Autodesk Fusion 360 part; units mm, degrees
(part 2 of 2)
  spline S171 degree 3 poles (-47.6297, 29.4828) (-47.5303, 29.3502) (-47.5255, 29.3502) (-46.4124, 28.9712) knots 0 0 0 0 1 1 1 1
  spline S172 degree 3 poles (-46.4124, 28.9712) (-46.0051, 28.8339) (-45.6546, 28.706) (-45.6403, 28.6918) knots 0 0 0 0 1 1 1 1
  spline S173 degree 3 poles (-45.6403, 28.6918) (-45.6072, 28.6586) (-45.5835, 28.6634) (-46.6398, 28.4692) knots 0 0 0 0 1 1 1 1
  spline S174 degree 3 poles (-46.6398, 28.4692) (-48.1413, 28.1944) (-48.7571, 28.0571) (-48.8281, 27.9813) knots 0 0 0 0 1 1 1 1
  spline S175 degree 3 poles (-48.8281, 27.9813) (-48.9086, 27.9008) (-48.9228, 27.6308) (-48.8518, 27.5597) knots 0 0 0 0 1 1 1 1
  spline S176 degree 3 poles (-48.8518, 27.5597) (-48.8281, 27.536) (-48.3308, 27.3561) (-47.7481, 27.1619) knots 0 0 0 0 1 1 1 1
  spline S177 degree 3 poles (-47.7481, 27.1619) (-47.1655, 26.9676) (-46.6824, 26.7971) (-46.6729, 26.7877) knots 0 0 0 0 1 1 1 1
  spline S178 degree 3 poles (-46.6729, 26.7877) (-46.6635, 26.7782) (-46.7392, 26.7261) (-46.8387, 26.674) knots 0 0 0 0 1 1 1 1
  spline S179 degree 3 poles (-46.8387, 26.674) (-47.1561, 26.5129) (-47.1561, 26.5129) (-47.1845, 25.4993) knots 0 0 0 0 1 1 1 1
  line L126 (-47.1845, 25.4993) -> (-47.2082, 24.5804)
  line L127 (-47.2082, 24.5804) -> (-47.6818, 24.9783)
  spline S180 degree 3 poles (-47.6818, 24.9783) (-48.9465, 26.0487) (-50.5001, 27.6355) (-50.5807, 27.9387) knots 0 0 0 0 1 1 1 1
  spline S181 degree 3 poles (-50.5807, 27.9387) (-50.5949, 28.005) (-50.5712, 28.1187) (-50.5191, 28.2181) knots 0 0 0 0 1 1 1 1
  spline S182 degree 3 poles (-50.5191, 28.2181) (-50.3154, 28.6018) (-48.6813, 30.2549) (-47.8334, 30.9322) knots 0 0 0 0 1 1 1 1
  line L128 (-47.8334, 30.9322) -> (-47.5682, 31.1454)
  line L129 (-47.5682, 31.1454) -> (-47.5634, 31.5669)
  line L130 (-47.5634, 31.5669) -> (-47.5634, 31.9838)
  line L131 (-47.5634, 31.9838) -> (-47.7908, 31.8038)
  spline S183 degree 3 poles (-47.7908, 31.8038) (-48.3071, 31.3869) (-49.387, 30.3733) (-50.0786, 29.6675) knots 0 0 0 0 1 1 1 1
  spline S184 degree 3 poles (-50.0786, 29.6675) (-51.3385, 28.3697) (-51.4759, 28.0381) (-51.0022, 27.3939) knots 0 0 0 0 1 1 1 1
  spline S185 degree 3 poles (-51.0022, 27.3939) (-50.5143, 26.7261) (-48.6386, 24.9214) (-47.3976, 23.922) knots 0 0 0 0 1 1 1 1
  spline S186 degree 3 poles (-47.3976, 23.922) (-46.0572, 22.842) (-45.5219, 22.5957) (-44.5035, 22.5957) knots 0 0 0 0 1 1 1 1
  spline S187 degree 3 poles (-44.5035, 22.5957) (-44.0583, 22.5957) (-43.9352, 22.6147) (-43.5941, 22.7331) knots 0 0 0 0 1 1 1 1
  spline S188 degree 3 poles (-43.5941, 22.7331) (-42.5521, 23.0978) (-41.8463, 23.903) (-41.6237, 24.9783) knots 0 0 0 0 1 1 1 1
  spline S189 degree 3 poles (-41.6237, 24.9783) (-41.4295, 25.9066) (-41.6521, 26.7545) (-42.3152, 27.6213) knots 0 0 0 0 1 1 1 1
  line L132 (-42.3152, 27.6213) -> (-42.6278, 28.0334)
  line L133 (-42.6278, 28.0334) -> (-42.4857, 28.166)
  spline S190 degree 3 poles (-42.4857, 28.166) (-42.32, 28.3271) (-41.9837, 28.8291) (-41.8416, 29.1323) knots 0 0 0 0 1 1 1 1
  spline S191 degree 3 poles (-41.8416, 29.1323) (-41.6095, 29.6249) (-41.5005, 30.4396) (-41.6, 30.9748) knots 0 0 0 0 1 1 1 1
  spline S192 degree 3 poles (-42.3152, 24.8267) (-42.4431, 24.4478) (-42.6136, 24.1825) (-42.9262, 23.8746) knots 0 0 0 0 1 1 1 1
  spline S193 degree 3 poles (-42.9262, 23.8746) (-43.4236, 23.382) (-43.9873, 23.1783) (-44.7214, 23.2257) knots 0 0 0 0 1 1 1 1
  spline S194 degree 3 poles (-44.7214, 23.2257) (-45.1998, 23.2541) (-45.5693, 23.3773) (-46.0003, 23.6615) knots 0 0 0 0 1 1 1 1
  spline S195 degree 3 poles (-46.0003, 23.6615) (-46.545, 24.0215) (-46.5119, 23.9315) (-46.5308, 25.144) knots 0 0 0 0 1 1 1 1
  line L134 (-46.5308, 25.144) -> (-46.545, 26.1956)
  line L135 (-46.545, 26.1956) -> (-46.223, 26.3661)
  spline S196 degree 3 poles (-46.223, 26.3661) (-46.0477, 26.4561) (-45.8724, 26.584) (-45.8298, 26.6456) knots 0 0 0 0 1 1 1 1
  spline S197 degree 3 poles (-45.8298, 26.6456) (-45.7351, 26.7924) (-45.7777, 27.015) (-45.9245, 27.1097) knots 0 0 0 0 1 1 1 1
  spline S198 degree 3 poles (-45.9245, 27.1097) (-45.9814, 27.1476) (-46.384, 27.2945) (-46.8198, 27.4318) knots 0 0 0 0 1 1 1 1
  spline S199 degree 3 poles (-46.8198, 27.4318) (-47.5587, 27.6639) (-47.7529, 27.7587) (-47.5066, 27.7587) knots 0 0 0 0 1 1 1 1
  spline S200 degree 3 poles (-47.5066, 27.7587) (-47.4071, 27.7587) (-47.0945, 27.8155) (-46.0951, 28.0192) knots 0 0 0 0 1 1 1 1
  spline S201 degree 3 poles (-46.0951, 28.0192) (-44.7546, 28.2892) (-44.5509, 28.3413) (-44.4704, 28.4123) knots 0 0 0 0 1 1 1 1
  spline S202 degree 3 poles (-44.4704, 28.4123) (-44.3472, 28.5213) (-44.3662, 28.7818) (-44.4988, 28.8718) knots 0 0 0 0 1 1 1 1
  spline S203 degree 3 poles (-44.4988, 28.8718) (-44.5888, 28.9286) (-46.815, 29.7007) (-46.9003, 29.7007) knots 0 0 0 0 1 1 1 1
  spline S204 degree 3 poles (-46.9003, 29.7007) (-46.9098, 29.7007) (-46.8435, 29.7528) (-46.7535, 29.8144) knots 0 0 0 0 1 1 1 1
  spline S205 degree 3 poles (-46.7535, 29.8144) (-46.5403, 29.9612) (-46.5214, 30.0749) (-46.5214, 31.169) knots 0 0 0 0 1 1 1 1
  line L136 (-46.5214, 31.169) -> (-46.5214, 31.9648)
  line L137 (-46.5214, 31.9648) -> (-46.223, 32.1874)
  spline S206 degree 3 poles (-46.223, 32.1874) (-45.6688, 32.5995) (-45.1572, 32.7795) (-44.5414, 32.7795) knots 0 0 0 0 1 1 1 1
  spline S207 degree 3 poles (-44.5414, 32.7795) (-43.6367, 32.7795) (-42.8078, 32.249) (-42.4147, 31.4248) knots 0 0 0 0 1 1 1 1
  spline S208 degree 3 poles (-42.4147, 31.4248) (-42.2489, 31.0791) (-42.2347, 31.0127) (-42.2205, 30.5485) knots 0 0 0 0 1 1 1 1
  spline S209 degree 3 poles (-42.2205, 30.5485) (-42.1921, 29.767) (-42.3436, 29.3454) (-42.9026, 28.6492) knots 0 0 0 0 1 1 1 1
  spline S210 degree 3 poles (-42.9026, 28.6492) (-43.0778, 28.436) (-43.2341, 28.2086) (-43.2531, 28.1423) knots 0 0 0 0 1 1 1 1
  spline S211 degree 3 poles (-43.2531, 28.1423) (-43.3052, 27.9434) (-43.2247, 27.7539) (-42.9405, 27.4271) knots 0 0 0 0 1 1 1 1
  spline S212 degree 3 poles (-42.9405, 27.4271) (-42.6563, 27.0955) (-42.4005, 26.6645) (-42.3057, 26.3614) knots 0 0 0 0 1 1 1 1
  spline S213 degree 3 poles (-42.3057, 26.3614) (-42.1542, 25.8877) (-42.1542, 25.2814) (-42.3152, 24.8267) knots 0 0 0 0 1 1 1 1
  line L138 (-47.5871, 5.9227) -> (-49.226, 5.9227)
  line L139 (-49.226, 5.9227) -> (-49.2118, 5.648)
  spline S214 degree 3 poles (-49.2118, 5.648) (-49.1976, 5.3828) (-49.1976, 5.378) (-49.0365, 5.3544) knots 0 0 0 0 1 1 1 1
  line L140 (-49.0365, 5.3544) -> (-48.8802, 5.3307)
  line L141 (-48.8802, 5.3307) -> (-48.9844, 5.2359)
  spline S215 degree 3 poles (-48.9844, 5.2359) (-49.3586, 4.9044) (-49.2733, 4.1986) (-48.8281, 3.8907) knots 0 0 0 0 1 1 1 1
  spline S216 degree 3 poles (-48.8281, 3.8907) (-48.5344, 3.6918) (-48.3071, 3.635) (-47.9234, 3.6586) knots 0 0 0 0 1 1 1 1
  spline S217 degree 3 poles (-47.9234, 3.6586) (-47.4118, 3.6918) (-47.085, 3.8955) (-46.924, 4.2744) knots 0 0 0 0 1 1 1 1
  spline S218 degree 3 poles (-46.924, 4.2744) (-46.7913, 4.6012) (-46.8482, 4.9328) (-47.0803, 5.1744) knots 0 0 0 0 1 1 1 1
  line L142 (-47.0803, 5.1744) -> (-47.2034, 5.307)
  line L143 (-47.2034, 5.307) -> (-46.5782, 5.307)
  line L144 (-46.5782, 5.307) -> (-45.953, 5.307)
  line L145 (-45.953, 5.307) -> (-45.953, 5.6149)
  line L146 (-45.953, 5.6149) -> (-45.953, 5.9227)
  line L147 (-45.953, 5.9227) -> (-47.5871, 5.9227)
  spline S219 degree 3 poles (-47.4876, 4.4875) (-47.7245, 4.2318) (-48.2787, 4.2128) (-48.5202, 4.4591) knots 0 0 0 0 1 1 1 1
  spline S220 degree 3 poles (-48.5202, 4.4591) (-48.7097, 4.6439) (-48.7097, 4.9517) (-48.5202, 5.1317) knots 0 0 0 0 1 1 1 1
  spline S221 degree 3 poles (-48.5202, 5.1317) (-48.2692, 5.3686) (-47.6724, 5.3449) (-47.4734, 5.0844) knots 0 0 0 0 1 1 1 1
  spline S222 degree 3 poles (-47.4734, 5.0844) (-47.3361, 4.9138) (-47.3408, 4.6439) (-47.4876, 4.4875) knots 0 0 0 0 1 1 1 1
  spline S223 degree 3 poles (-46.1282, 21.8568) (-46.2372, 21.89) (-49.027, 21.89) (-49.136, 21.8568) knots 0 0 0 0 1 1 1 1
  spline S224 degree 3 poles (-49.136, 21.8568) (-49.207, 21.8379) (-49.2212, 21.7763) (-49.2212, 21.5252) knots 0 0 0 0 1 1 1 1
  line L148 (-49.2212, 21.5252) -> (-49.2212, 21.2221)
  line L149 (-49.2212, 21.2221) -> (-48.5107, 21.2221)
  line L150 (-48.5107, 21.2221) -> (-47.7955, 21.2221)
  line L151 (-47.7955, 21.2221) -> (-47.8097, 20.4974)
  line L152 (-47.8097, 20.4974) -> (-47.8239, 19.7774)
  line L153 (-47.8239, 19.7774) -> (-48.525, 19.7632)
  line L154 (-48.525, 19.7632) -> (-49.226, 19.749)
  line L155 (-49.226, 19.749) -> (-49.2118, 19.4317)
  line L156 (-49.2118, 19.4317) -> (-49.1976, 19.1143)
  line L157 (-49.1976, 19.1143) -> (-47.6203, 19.1001)
  line L158 (-47.6203, 19.1001) -> (-46.0477, 19.0906)
  line L159 (-46.0477, 19.0906) -> (-46.0477, 19.4222)
  line L160 (-46.0477, 19.4222) -> (-46.0477, 19.749)
  line L161 (-46.0477, 19.749) -> (-46.6256, 19.7632)
  line L162 (-46.6256, 19.7632) -> (-47.2082, 19.7774)
  line L163 (-47.2082, 19.7774) -> (-47.2082, 20.4879)
  line L164 (-47.2082, 20.4879) -> (-47.2082, 21.1984)
  line L165 (-47.2082, 21.1984) -> (-46.6256, 21.2126)
  line L166 (-46.6256, 21.2126) -> (-46.0477, 21.2268)
  line L167 (-46.0477, 21.2268) -> (-46.0477, 21.53)
  spline S225 degree 3 poles (-46.0477, 21.53) (-46.0477, 21.7763) (-46.0619, 21.8379) (-46.1282, 21.8568) knots 0 0 0 0 1 1 1 1
  line L168 (-47.6345, 10.4699) -> (-49.2212, 10.4699)
  line L169 (-49.2212, 10.4699) -> (-49.2212, 9.5463)
  line L170 (-49.2212, 9.5463) -> (-49.2212, 8.6226)
  line L171 (-49.2212, 8.6226) -> (-48.9134, 8.6226)
  line L172 (-48.9134, 8.6226) -> (-48.6055, 8.6226)
  line L173 (-48.6055, 8.6226) -> (-48.6055, 9.2384)
  line L174 (-48.6055, 9.2384) -> (-48.6055, 9.8542)
  line L175 (-48.6055, 9.8542) -> (-47.3266, 9.8542)
  line L176 (-47.3266, 9.8542) -> (-46.0477, 9.8542)
  line L177 (-46.0477, 9.8542) -> (-46.0477, 10.162)
  line L178 (-46.0477, 10.162) -> (-46.0477, 10.4699)
  line L179 (-46.0477, 10.4699) -> (-47.6345, 10.4699)
  spline S226 degree 3 poles (-46.3603, 11.9714) (-46.3793, 12.0093) (-46.4835, 12.033) (-46.6398, 12.033) knots 0 0 0 0 1 1 1 1
  spline S227 degree 3 poles (-46.6398, 12.033) (-46.8908, 12.033) (-46.8956, 12.033) (-46.9098, 12.1846) knots 0 0 0 0 1 1 1 1
  spline S228 degree 3 poles (-46.9098, 12.1846) (-46.9192, 12.2698) (-46.9382, 12.3362) (-46.9571, 12.3267) knots 0 0 0 0 1 1 1 1
  spline S229 degree 3 poles (-46.9571, 12.3267) (-46.9808, 12.322) (-47.0803, 12.3172) (-47.1845, 12.3172) knots 0 0 0 0 1 1 1 1
  spline S230 degree 3 poles (-47.1845, 12.3172) (-47.3597, 12.3172) (-47.374, 12.3077) (-47.374, 12.1799) knots 0 0 0 0 1 1 1 1
  line L180 (-47.374, 12.1799) -> (-47.374, 12.0425)
  line L181 (-47.374, 12.0425) -> (-48.0466, 12.0235)
  spline S231 degree 3 poles (-48.0466, 12.0235) (-48.8044, 12.0046) (-48.937, 11.9667) (-49.1123, 11.7062) knots 0 0 0 0 1 1 1 1
  spline S232 degree 3 poles (-49.1123, 11.7062) (-49.1928, 11.5878) (-49.2212, 11.4788) (-49.2212, 11.2799) knots 0 0 0 0 1 1 1 1
  spline S233 degree 3 poles (-49.2212, 11.2799) (-49.2212, 10.8299) (-49.2023, 10.8015) (-48.9086, 10.8015) knots 0 0 0 0 1 1 1 1
  line L182 (-48.9086, 10.8015) -> (-48.6528, 10.8015)
  line L183 (-48.6528, 10.8015) -> (-48.6528, 11.0288)
  spline S234 degree 3 poles (-48.6528, 11.0288) (-48.6528, 11.152) (-48.6292, 11.2799) (-48.596, 11.313) knots 0 0 0 0 1 1 1 1
  spline S235 degree 3 poles (-48.596, 11.313) (-48.5581, 11.3509) (-48.345, 11.3699) (-47.9566, 11.3699) knots 0 0 0 0 1 1 1 1
  line L184 (-47.9566, 11.3699) -> (-47.374, 11.3699)
  line L185 (-47.374, 11.3699) -> (-47.374, 11.081)
  line L186 (-47.374, 11.081) -> (-47.374, 10.7968)
  line L187 (-47.374, 10.7968) -> (-47.1466, 10.811)
  line L188 (-47.1466, 10.811) -> (-46.924, 10.8252)
  line L189 (-46.924, 10.8252) -> (-46.9098, 11.0952)
  line L190 (-46.9098, 11.0952) -> (-46.8956, 11.3651)
  line L191 (-46.8956, 11.3651) -> (-46.6256, 11.3794)
  line L192 (-46.6256, 11.3794) -> (-46.3556, 11.3936)
  line L193 (-46.3556, 11.3936) -> (-46.3461, 11.6541)
  spline S236 degree 3 poles (-46.3461, 11.6541) (-46.3414, 11.7962) (-46.3508, 11.943) (-46.3603, 11.9714) knots 0 0 0 0 1 1 1 1
  spline S237 degree 3 poles (-46.9145, 18.0864) (-47.0755, 18.527) (-47.5113, 18.8064) (-48.0371, 18.8064) knots 0 0 0 0 1 1 1 1
  spline S238 degree 3 poles (-48.0371, 18.8064) (-48.7665, 18.8017) (-49.2212, 18.3422) (-49.2212, 17.608) knots 0 0 0 0 1 1 1 1
  spline S239 degree 3 poles (-49.2212, 17.608) (-49.2212, 17.4328) (-49.1928, 17.2196) (-49.1597, 17.1344) knots 0 0 0 0 1 1 1 1
  spline S240 degree 3 poles (-49.1597, 17.1344) (-49.0791, 16.9497) (-48.8518, 16.6749) (-48.7807, 16.6749) knots 0 0 0 0 1 1 1 1
  spline S241 degree 3 poles (-48.7807, 16.6749) (-48.7476, 16.6749) (-48.6765, 16.7507) (-48.615, 16.8454) knots 0 0 0 0 1 1 1 1
  line L194 (-48.615, 16.8454) -> (-48.506, 17.0112)
  line L195 (-48.506, 17.0112) -> (-48.6007, 17.2149)
  spline S242 degree 3 poles (-48.6007, 17.2149) (-48.7713, 17.5654) (-48.705, 17.9396) (-48.4444, 18.1149) knots 0 0 0 0 1 1 1 1
  spline S243 degree 3 poles (-48.4444, 18.1149) (-48.1887, 18.2806) (-48.1792, 18.2617) (-48.1792, 17.4091) knots 0 0 0 0 1 1 1 1
  line L196 (-48.1792, 17.4091) -> (-48.1792, 16.6276)
  line L197 (-48.1792, 16.6276) -> (-47.895, 16.6276)
  spline S244 degree 3 poles (-47.895, 16.6276) (-47.2745, 16.6276) (-46.8529, 17.0539) (-46.8577, 17.6696) knots 0 0 0 0 1 1 1 1
  spline S245 degree 3 poles (-46.8577, 17.6696) (-46.8577, 17.8117) (-46.8861, 18.0012) (-46.9145, 18.0864) knots 0 0 0 0 1 1 1 1
  spline S246 degree 3 poles (-47.374, 17.4281) (-47.4355, 17.3238) (-47.6913, 17.1817) (-47.7529, 17.2196) knots 0 0 0 0 1 1 1 1
  spline S247 degree 3 poles (-47.7529, 17.2196) (-47.8192, 17.2623) (-47.8145, 18.1907) (-47.7481, 18.1907) knots 0 0 0 0 1 1 1 1
  spline S248 degree 3 poles (-47.7481, 18.1907) (-47.6629, 18.1907) (-47.4971, 18.0912) (-47.4118, 17.9822) knots 0 0 0 0 1 1 1 1
  spline S249 degree 3 poles (-47.4118, 17.9822) (-47.3171, 17.8733) (-47.2982, 17.5702) (-47.374, 17.4281) knots 0 0 0 0 1 1 1 1
  spline S250 degree 3 poles (-46.8956, 15.7276) (-46.9666, 15.9502) (-47.0898, 16.1539) (-47.2129, 16.2297) knots 0 0 0 0 1 1 1 1
  spline S251 degree 3 poles (-47.2129, 16.2297) (-47.3503, 16.3197) (-47.3313, 16.3292) (-47.464, 16.0734) knots 0 0 0 0 1 1 1 1
  line L198 (-47.464, 16.0734) -> (-47.5634, 15.8744)
  line L199 (-47.5634, 15.8744) -> (-47.445, 15.756)
  spline S252 degree 3 poles (-47.445, 15.756) (-47.2745, 15.5855) (-47.2745, 15.2066) (-47.445, 15.0408) knots 0 0 0 0 1 1 1 1
  spline S253 degree 3 poles (-47.445, 15.0408) (-47.5066, 14.9745) (-47.6108, 14.9224) (-47.6771, 14.9224) knots 0 0 0 0 1 1 1 1
  spline S254 degree 3 poles (-47.6771, 14.9224) (-47.7908, 14.9224) (-47.7955, 14.9271) (-47.7955, 15.3487) knots 0 0 0 0 1 1 1 1
  spline S255 degree 3 poles (-47.7955, 15.3487) (-47.7955, 15.7087) (-47.8097, 15.8081) (-47.9045, 15.9739) knots 0 0 0 0 1 1 1 1
  spline S256 degree 3 poles (-47.9045, 15.9739) (-48.1981, 16.5091) (-48.8707, 16.5328) (-49.1407, 16.0118) knots 0 0 0 0 1 1 1 1
  spline S257 degree 3 poles (-49.1407, 16.0118) (-49.2686, 15.7608) (-49.2355, 15.3155) (-49.0649, 15.0976) knots 0 0 0 0 1 1 1 1
  spline S258 degree 3 poles (-49.0649, 15.0976) (-48.9939, 15.0029) (-48.937, 14.9176) (-48.937, 14.9034) knots 0 0 0 0 1 1 1 1
  spline S259 degree 3 poles (-48.937, 14.9034) (-48.937, 14.8892) (-48.9986, 14.875) (-49.0791, 14.875) knots 0 0 0 0 1 1 1 1
  line L200 (-49.0791, 14.875) -> (-49.2212, 14.875)
  line L201 (-49.2212, 14.875) -> (-49.2212, 14.5908)
  line L202 (-49.2212, 14.5908) -> (-49.2212, 14.3066)
  line L203 (-49.2212, 14.3066) -> (-48.3781, 14.3066)
  spline S260 degree 3 poles (-48.3781, 14.3066) (-47.4829, 14.3066) (-47.2792, 14.3492) (-47.0755, 14.5813) knots 0 0 0 0 1 1 1 1
  spline S261 degree 3 poles (-47.0755, 14.5813) (-46.8861, 14.7945) (-46.7913, 15.3866) (-46.8956, 15.7276) knots 0 0 0 0 1 1 1 1
  spline S262 degree 3 poles (-48.2502, 14.9413) (-48.3781, 14.8892) (-48.5534, 14.9697) (-48.6292, 15.1118) knots 0 0 0 0 1 1 1 1
  spline S263 degree 3 poles (-48.6292, 15.1118) (-48.7239, 15.2918) (-48.7192, 15.6044) (-48.6244, 15.6992) knots 0 0 0 0 1 1 1 1
  spline S264 degree 3 poles (-48.6244, 15.6992) (-48.5202, 15.8081) (-48.3402, 15.7939) (-48.255, 15.6708) knots 0 0 0 0 1 1 1 1
  spline S265 degree 3 poles (-48.255, 15.6708) (-48.1508, 15.5239) (-48.1508, 14.9792) (-48.2502, 14.9413) knots 0 0 0 0 1 1 1 1
  spline S266 degree 3 poles (-46.8861, 12.8714) (-46.8956, 12.9282) (-46.9808, 13.0419) (-47.0708, 13.1177) knots 0 0 0 0 1 1 1 1
  spline S267 degree 3 poles (-47.0708, 13.1177) (-47.1608, 13.1982) (-47.2319, 13.274) (-47.2319, 13.2882) knots 0 0 0 0 1 1 1 1
  spline S268 degree 3 poles (-47.2319, 13.2882) (-47.2319, 13.3024) (-47.1561, 13.3119) (-47.0661, 13.3119) knots 0 0 0 0 1 1 1 1
  line L204 (-47.0661, 13.3119) -> (-46.9003, 13.3119)
  line L205 (-46.9003, 13.3119) -> (-46.9003, 13.5961)
  line L206 (-46.9003, 13.5961) -> (-46.9003, 13.8803)
  line L207 (-46.9003, 13.8803) -> (-48.0608, 13.8803)
  line L208 (-48.0608, 13.8803) -> (-49.2212, 13.8803)
  line L209 (-49.2212, 13.8803) -> (-49.2212, 13.5724)
  line L210 (-49.2212, 13.5724) -> (-49.2212, 13.2645)
  line L211 (-49.2212, 13.2645) -> (-48.6055, 13.2645)
  spline S269 degree 3 poles (-48.6055, 13.2645) (-47.7481, 13.2645) (-47.5682, 13.1793) (-47.5161, 12.7482) knots 0 0 0 0 1 1 1 1
  line L212 (-47.5161, 12.7482) -> (-47.4924, 12.5304)
  line L213 (-47.4924, 12.5304) -> (-47.1703, 12.5162)
  line L214 (-47.1703, 12.5162) -> (-46.8529, 12.5019)
  line L215 (-46.8529, 12.5019) -> (-46.8577, 12.6346)
  spline S270 degree 3 poles (-46.8577, 12.6346) (-46.8624, 12.7056) (-46.8766, 12.8146) (-46.8861, 12.8714) knots 0 0 0 0 1 1 1 1
  spline S271 degree 3 poles (-46.9192, 7.8316) (-46.9903, 8.0258) (-47.0613, 8.1348) (-47.2082, 8.2532) knots 0 0 0 0 1 1 1 1
  spline S272 degree 3 poles (-47.2082, 8.2532) (-47.3361, 8.3669) (-47.3597, 8.3621) (-47.4355, 8.2058) knots 0 0 0 0 1 1 1 1
  spline S273 degree 3 poles (-47.4355, 8.2058) (-47.5539, 7.9785) (-47.5776, 7.8648) (-47.5018, 7.8648) knots 0 0 0 0 1 1 1 1
  spline S274 degree 3 poles (-47.5018, 7.8648) (-47.4071, 7.8648) (-47.3266, 7.6564) (-47.3266, 7.3911) knots 0 0 0 0 1 1 1 1
  spline S275 degree 3 poles (-47.3266, 7.3911) (-47.3266, 7.1969) (-47.3455, 7.1448) (-47.4497, 7.0643) knots 0 0 0 0 1 1 1 1
  spline S276 degree 3 poles (-47.4497, 7.0643) (-47.5208, 7.0074) (-47.625, 6.9648) (-47.6818, 6.9648) knots 0 0 0 0 1 1 1 1
  spline S277 degree 3 poles (-47.6818, 6.9648) (-47.786, 6.9648) (-47.7908, 6.979) (-47.7908, 7.3674) knots 0 0 0 0 1 1 1 1
  spline S278 degree 3 poles (-47.7908, 7.3674) (-47.7908, 8.0116) (-48.0229, 8.3716) (-48.4681, 8.419) knots 0 0 0 0 1 1 1 1
  spline S279 degree 3 poles (-48.4681, 8.419) (-48.7381, 8.4474) (-48.9702, 8.3195) (-49.1123, 8.0732) knots 0 0 0 0 1 1 1 1
  spline S280 degree 3 poles (-49.1123, 8.0732) (-49.2876, 7.77) (-49.2355, 7.249) (-49.0176, 7.0643) knots 0 0 0 0 1 1 1 1
  spline S281 degree 3 poles (-49.0176, 7.0643) (-48.9039, 6.9743) (-48.9181, 6.9269) (-49.0649, 6.908) knots 0 0 0 0 1 1 1 1
  spline S282 degree 3 poles (-49.0649, 6.908) (-49.1928, 6.8938) (-49.1976, 6.8796) (-49.2118, 6.619) knots 0 0 0 0 1 1 1 1
  line L216 (-49.2118, 6.619) -> (-49.226, 6.349)
  line L217 (-49.226, 6.349) -> (-48.4065, 6.349)
  spline S283 degree 3 poles (-48.4065, 6.349) (-47.9566, 6.349) (-47.5066, 6.3727) (-47.4118, 6.3964) knots 0 0 0 0 1 1 1 1
  spline S284 degree 3 poles (-47.4118, 6.3964) (-47.2034, 6.458) (-46.9713, 6.709) (-46.905, 6.9506) knots 0 0 0 0 1 1 1 1
  spline S285 degree 3 poles (-46.905, 6.9506) (-46.834, 7.1969) (-46.8435, 7.6137) (-46.9192, 7.8316) knots 0 0 0 0 1 1 1 1
  spline S286 degree 3 poles (-48.2502, 6.9838) (-48.3686, 6.9364) (-48.5534, 7.0074) (-48.6339, 7.1306) knots 0 0 0 0 1 1 1 1
  spline S287 degree 3 poles (-48.6339, 7.1306) (-48.7428, 7.2964) (-48.7286, 7.6185) (-48.615, 7.7369) knots 0 0 0 0 1 1 1 1
  spline S288 degree 3 poles (-48.615, 7.7369) (-48.4965, 7.8553) (-48.2881, 7.8127) (-48.2265, 7.6611) knots 0 0 0 0 1 1 1 1
  spline S289 degree 3 poles (-48.2265, 7.6611) (-48.1555, 7.4811) (-48.1697, 7.0122) (-48.2502, 6.9838) knots 0 0 0 0 1 1 1 1
extrude "Extrusão10'" cut sketch "Esboço11" against normal blind 2 contours S0 L4 L5 S1 S2 S3 L6 L7 S4 L8 L9 S5 S6 | S7 S8 S9 L10 L11 L12 L13 S10 L14 L15 L16 L17 L18 L19 S11 S12 S13 S14 S15 L20 L21 S16 S17 L22 L23 S18 S19 S20 | S21 S22 S23 S24 S25 L24 L25 S26 S27 S28 S29 S30 S31 S32 S33 L26 L27 S34 | S35 S36 L28 L29 L30 L31 L32 L33 L34 L35 L36 L37 S37 L38 L39 L40 L41 | L42 L43 S38 S39 S40 | S41 S42 S43 L44 L45 L46 L47 S44 S45 S46 L48 L49 | S47 S48 S49 S50 S51 | S52 S53 L50 L51 S54 S55 S56 S57 S58 L52 L53 S59 S60 S61 S62 L54 L55 S63 S64 L56 L57 | S65 S66 S67 S68 L58 L59 S69 S70 S71 L60 L61 | S72 S73 S74 S75 S76 | S77 S78 S79 L62 L63 L64 L65 L66 L67 S80 S81 L68 L69 L70 L71 L72 L73 S82 S83 S84 S85 S86 S87 L74 L75 S88 S89 L76 L77 S90 S91 S92 | S93 S94 S95 S96 S97 L78 L79 L80 L81 S98 S99 L82 L83 L84 L85 S100 S101 S102 S103 S104 S105 L86 L87 L88 L89 L90 L91 S106 L92 L93 S107 S108 S109 S110 | S111 S112 S113 S114 S115 S116 L94 L95 S117 S118 S119 S120 L96 L97 L98 L99 S121 S122 | S123 S124 S125 S126 S127 S128 L100 L101 L102 L103 S129 S130 L104 L105 S131 S132 S133 L106 L107 S134 | S135 S136 L108 L109 S137 L110 L111 S138 S139 S140 L112 L113 | S141 S142 L114 L115 S143 S144 S145 | S146 S147 S148 S149 | S150 S151 S152 S153 S154 S155 S156 S157 L116 L117 S158 S159 L118 L119 L120 L121 S160 | S161 S162 S163 S164 S165 | S166 S167 S168 S169 L122 L123 L124 L125 S170 S171 S172 S173 S174 S175 S176 S177 S178 S179 L126 L127 S180 S181 S182 L128 L129 L130 L131 S183 S184 S185 S186 S187 S188 S189 L132 L133 S190 S191 | L138 L139 S214 L140 L141 S215 S216 S217 S218 L142 L143 L144 L145 L146 L147 | S219 S220 S221 S222 | S223 S224 L148 L149 L150 L151 L152 L153 L154 L155 L156 L157 L158 L159 L160 L161 L162 L163 L164 L165 L166 L167 S225 | L168 L169 L170 L171 L172 L173 L174 L175 L176 L177 L178 L179 | S226 S227 S228 S229 S230 L180 L181 S231 S232 S233 L182 L183 S234 S235 L184 L185 L186 L187 L188 L189 L190 L191 L192 L193 S236 | S237 S238 S239 S240 S241 L194 L195 S242 S243 L196 L197 S244 S245 | S246 S247 S248 S249 | S250 S251 L198 L199 S252 S253 S254 S255 S256 S257 S258 S259 L200 L201 L202 L203 S260 S261 | S262 S263 S264 S265 | S266 S267 S268 L204 L205 L206 L207 L208 L209 L210 L211 S269 L212 L213 L214 L215 S270 | S271 S272 S273 S274 S275 S276 S277 S278 S279 S280 S281 S282 L216 L217 S283 S284 S285 | S286 S287 S288 S289 bodies 6 makes body 7 at (45.28, 34, 30.9358) in component "Tampa"
component "Placa 5x7" placed x (1, 0, 0) y (0, 1, 0) z (0, 0, 1) at (0, 0, 0)
component "Tampa" placed x (1, 0, 0) y (0, 1, 0) z (0, 0, 1) at (0, 0, 0)
component "Suporte Placa (1)" placed x (1, 0, 0) y (0, 1, 0) z (0, 0, 1) at (0, 0, 0)
named bodies: "Placa 4x6"
